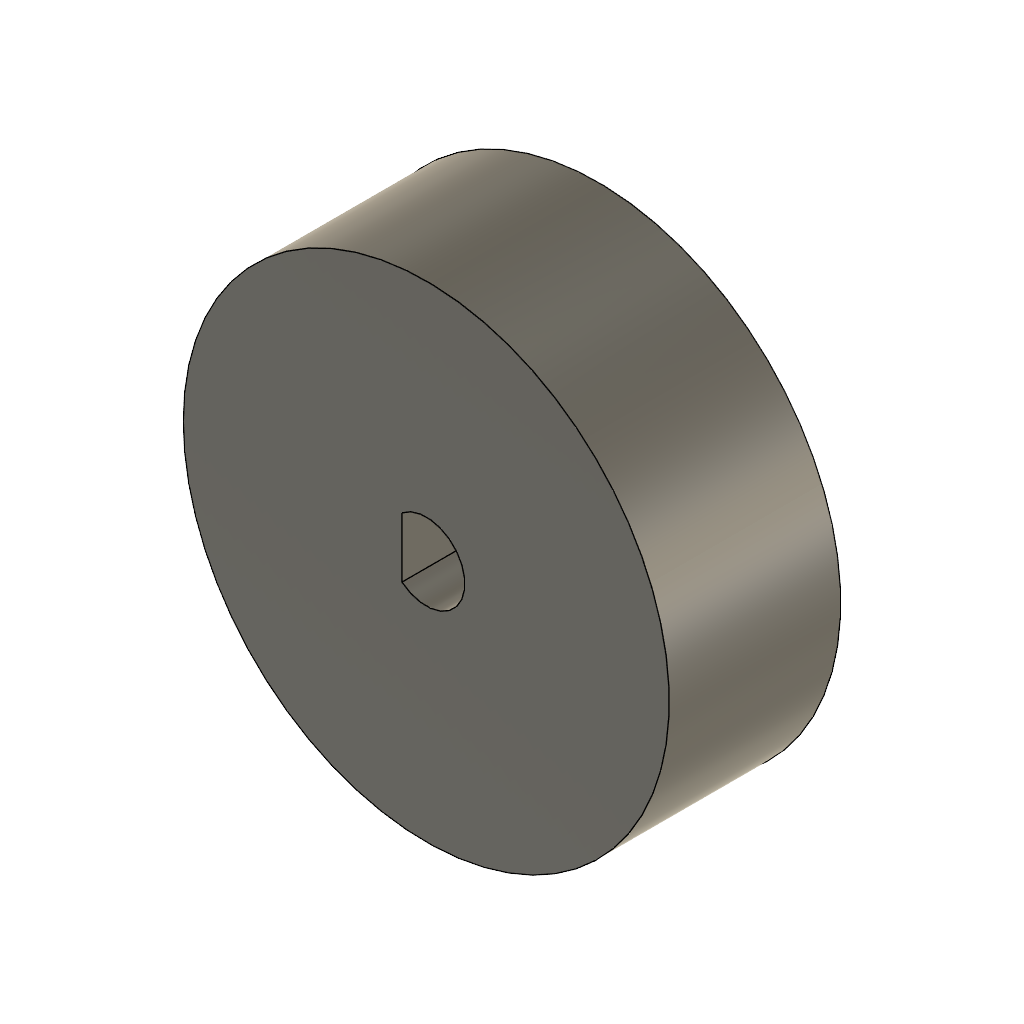
WheelType1 (Autodesk Fusion 360 design; units mm, degrees)
part number: 2026-10-04-00-19-53-659
Autodesk Fusion 360 part; units mm, degrees
sketch "Szkic1" plane through (0, 0, 0) normal (0, 1, 0) x (1, 0, 0)
  line L0 (-0.85, -0.9) -> (-0.85, -1.0488)
  line L1 (-0.85, 1.0488) -> (-0.85, -0.9)
  arc A0 (-0.85, -1.0488) -> (-0.85, 1.0488) centre (0, 0) ccw
  circle A1 centre (0, 0) radius 8.5
  dimension "d5" = 2.7
  dimension "d9" = 17
  constraint coincident A0.centre A1.centre
  constraint parallel L0 L1
  measures "d5" diameter of A0
  measures "d9" diameter of A1
extrude "Wyciągnięcie proste1" add sketch "Szkic1" along normal blind 6
